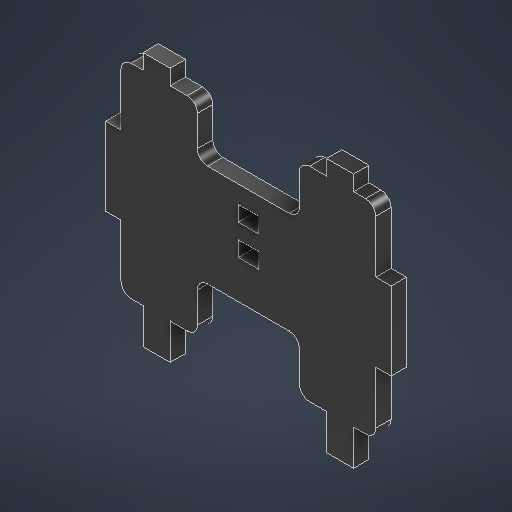
# Autodesk Inventor part: RxFace
Saved by Autodesk Inventor 2027.1 (Build 311270010, 270A)
## iProperties
Created: 2026-10-19
Part Number: RxFace
Material: MDF Medium Density Fiberboard
Document SubType Name: Modeling
Designer: SDS Scholar
Density: 0.8 g/cm^3
Appearance: Glossy - Black
Mass: 4.2427 g
Surface Area: 43.8923 cm^2
Volume: 5.30337 cm^3
Author: SDS Scholar
Autodesk Inventor part; units mm, degrees
ref_plane "YZ Plane" through (0, 0, 0) normal (1, 0, 0) x (0, 1, 0)
ref_plane "XZ Plane" through (0, 0, 0) normal (0, 1, 0) x (-1, 0, 0)
ref_plane "XY Plane" through (0, 0, 0) normal (0, 0, 1) x (1, 0, 0)
sketch "Sketch1" plane through (0, 0, 0) normal (0, 0, 1) x (1, 0, 0)
  line L0 (-25, 20) -> (25, 20)
  line L1 (25, 20) -> (25, -20)
  line L2 (25, -20) -> (-25, -20)
  line L3 (-25, -20) -> (-25, 20)
  line L4 (-10, -20) -> (10, -20)
  line L5 (10, -20) -> (10, -10)
  line L6 (10, -10) -> (-10, -10)
  line L7 (-10, -10) -> (-10, -20)
  line L8 (-25, 0) -> (25, 0) construction
  line L9 (0, 20) -> (0, -20) construction
  line L10 (-20.65, -20) -> (-15.35, -20)
  line L11 (-15.35, -20) -> (-15.35, -27)
  line L12 (-15.35, -27) -> (-20.65, -27)
  line L13 (-20.65, -27) -> (-20.65, -20)
  line L14 (-20.65, 20) -> (-15.35, 20)
  line L15 (-15.35, 20) -> (-15.35, 23)
  line L16 (-15.35, 23) -> (-20.65, 23)
  line L17 (-20.65, 23) -> (-20.65, 20)
  line L18 (-25, 7.65) -> (-28, 7.65)
  line L19 (-28, 7.65) -> (-28, -7.65)
  line L20 (-28, -7.65) -> (-25, -7.65)
  line L21 (-25, -7.65) -> (-25, 7.65)
  line L22 (15.35, -20) -> (15.35, -27)
  line L23 (15.35, -27) -> (20.65, -27)
  line L24 (20.65, -27) -> (20.65, -20)
  line L25 (15.35, 20) -> (15.35, 23)
  line L26 (15.35, 23) -> (20.65, 23)
  line L27 (20.65, 23) -> (20.65, 20)
  line L28 (25, 7.65) -> (28, 7.65)
  line L29 (28, 7.65) -> (28, -7.65)
  line L30 (28, -7.65) -> (25, -7.65)
  line L31 (10, 20) -> (10, 10)
  line L32 (10, 10) -> (-10, 10)
  line L33 (-10, 10) -> (-10, 20)
  line L34 (-2, 6.5) -> (2, 6.5)
  line L35 (2, 6.5) -> (2, 3.5)
  line L36 (2, 3.5) -> (-2, 3.5)
  line L37 (-2, 3.5) -> (-2, 6.5)
  line L38 (-2, 0.5) -> (2, 0.5)
  line L39 (2, 0.5) -> (2, -2.5)
  line L40 (2, -2.5) -> (-2, -2.5)
  line L41 (-2, -2.5) -> (-2, 0.5)
  point P0 (0, 0)
  point P1 (0, -10)
  point P2 (-18, -27)
  point P3 (-18, 23)
  point P4 (-28, 0)
  point P5 (0, 0)
  point P6 (15.35, -20)
  point P7 (20.65, -20)
  point P8 (25, -7.65)
  point P9 (25, 7.65)
  point P10 (-15.35, 20)
  point P11 (-25, -7.65)
  point P12 (0, 6.5)
  point P13 (0, 0)
  point P14 (2, 5)
  point P15 (0, 3.5)
  point P16 (0, 0.5)
  point P17 (18, -27)
  dimension "d0" = 50
  dimension "d1" = 40
  dimension "d2" = 10
  dimension "d3" = 20
  dimension "d4" = 7
  dimension "d5" = 5.3
  dimension "d7" = 3
  dimension "d8" = 5.3
  dimension "d9" = 15.3
  dimension "d10" = 3
  dimension "d15" = 3
  dimension "d16" = 4
  dimension "d17" = 5
  dimension "d18" = 4
  dimension "d19" = 3
  dimension "d20" = 3
  dimension "d21" = 36
  constraints: 84 end point, 16 symmetric about line, 15 midpoint, 14 parallel, 8 horizontal, 8 perpendicular, 5 vertical alignment, 4 point on line, 2 horizontal alignment
  measures "d0" distance of L1.end L2.end
  measures "d1" distance of L0.end L1.end
  measures "d2" distance of L6.end L4.start
  measures "d3" distance of L5.end L6.end
  measures "d4" distance of L12.end L10.start
  measures "d5" distance of L11.end L12.end
  measures "d7" distance of L14.end L15.end
  measures "d8" distance of L15.end L16.end
  measures "d9" distance of L18.end L19.end
  measures "d10" distance of L19.end L20.end
  measures "d15" distance of L34.end L35.end
  measures "d16" distance of L34.start L34.end
  measures "d17" distance from line of L32 point (2, 5)
  measures "d18" distance of L39.end L40.end
  measures "d19" distance of L38.end L39.end
  measures "d20" distance between parallel lines of L36 L38
  measures "d21" distance of point (18, -27) point (-18, -27)
extrude "Extrusion1" add sketch "Sketch1" along normal blind 3 contours L0 L33 L32 L31 L1 L2 L5 L6 L7 L3 | L17 L16 L15 L0 | L3 L20 L19 L18 | L2 L11 L12 L13 | L25 L26 L27 L0 | L28 L29 L30 L1 | L2 L24 L23 L22
fillet "Fillet1" [suppressed]
fillet "Fillet2" radius 2 12 edges at (-25, -20, 1.5) (-10, -20, 1.5) (10, -20, 1.5) (25, -20, 1.5) (10, -10, 1.5) (-10, -10, 1.5) (25, 20, 1.5) (10, 20, 1.5) (-10, 20, 1.5) (-25, 20, 1.5) (10, 10, 1.5) (-10, 10, 1.5)
equation "\"d0\" = Product_dia"
equation "\"d1\" = ProductBaseHeight"
equation "\"d4\" = BaseWoodThickness"
equation "\"Product_dia\" = 50"
equation "\"ProductBaseHeight\" = 40"
equation "\"GridProcutClearance\" = 5"
equation "\"GridBorderThickness\" = 5"
equation "\"GridBorderFillets\" = 7"
equation "\"GridTotalSize\" = 65"
equation "\"GridRobotClearance\" = 65"
equation "\"AluminiumExtrusionClearance\" = 35"
equation "\"BaseTotalLength\" = 885"
equation "\"WorkspaceLength\" = 515"
equation "\"WorkspaceHeight\" = 183"
equation "\"AxesBaseFillet\" = 15"
equation "\"Zaxis\" = 197"
equation "\"ProductTotalHeight\" = 45"
equation "\"VerticalStroke\" = 105"
equation "\"BackArea\" = 165"
equation "\"CylinderStroke\" = 75"
equation "\"BoxesWidth\" = 125"
equation "\"BaseWoodThickness\" = 7"
equation "\"Kerf\" = 0.3"
equation "\"RxThickness\" = 1.8"
equation "\"support_2\" = 265"
body "Solid1"
